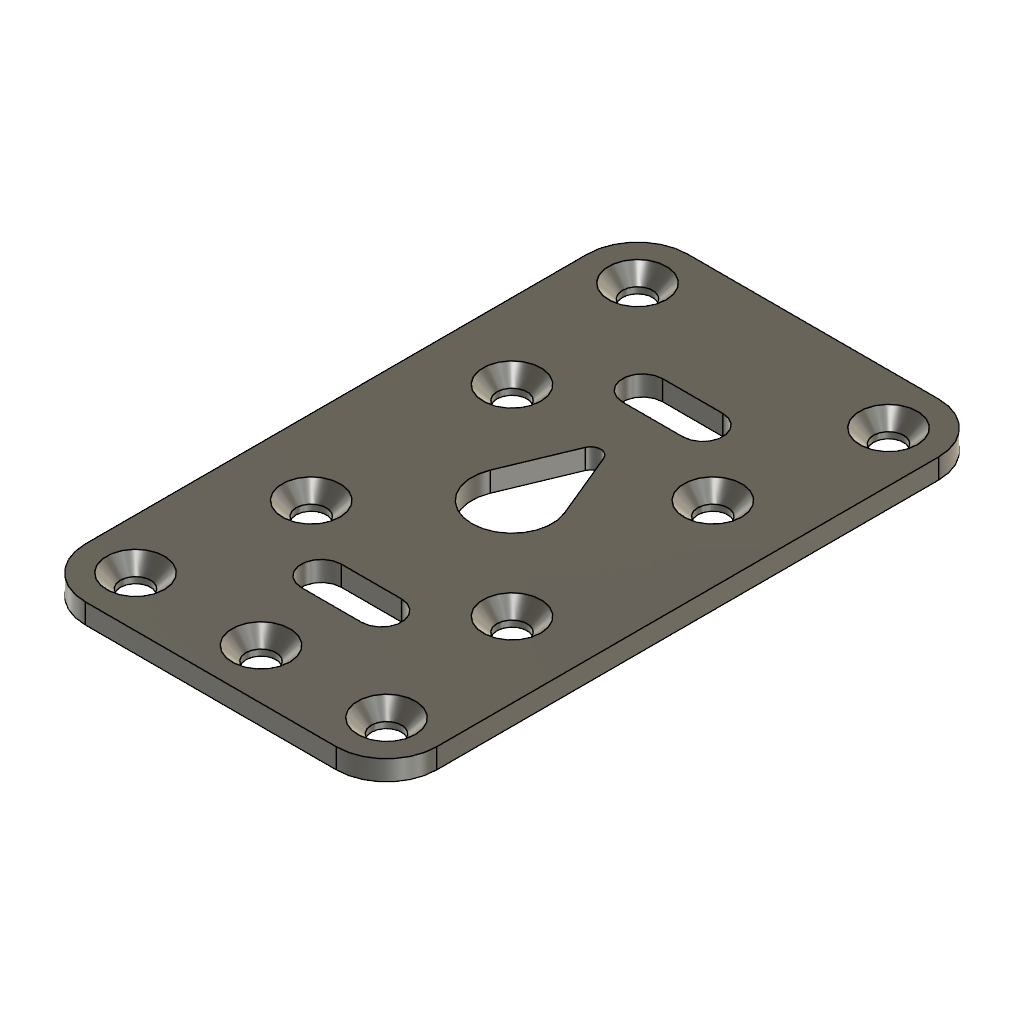
bottom plate (Autodesk Fusion 360 design; units mm, degrees)
part number: 2026-08-28-11-00-39-377
Autodesk Fusion 360 part; units mm, degrees
sketch "Sketch2" plane through (0, 0, 0) normal (0, 0, 1) x (1, 0, 0)
  line L0 (0, 0) -> (35, 0)
  line L1 (35, 0) -> (35, 60)
  line L2 (35, 60) -> (0, 60)
  line L3 (0, 60) -> (0, 0)
  dimension "d1" = 35
  dimension "d2" = 60
  constraint horizontal L0
  constraint vertical L1
  constraint horizontal L2
  constraint vertical L3
  constraint coincident L0.start L3.end
  measures "d1" distance of L0.start L0.end
  measures "d2" distance of L0.end L1.end
extrude "Extrude1" add sketch "Sketch2" along normal blind 2
sketch "Sketch3" plane through (0, 0, 2) normal (0, 0, 1) x (-1, 0, 0)
  line L0 (0, -60) -> (0, 0)
  line L1 (0, 0) -> (-35, 0)
  line L2 (-35, 0) -> (-35, -60)
  line L3 (-35, -60) -> (0, -60)
  point P0 (-5, -5)
  point P1 (-17.5, -5)
  point P2 (-30, -5)
  point P3 (-5, -55)
  point P4 (-30, -55)
  point P5 (-7.5, -40)
  point P6 (-27.5, -40)
  point P7 (-7.5, -20)
  point P8 (-27.5, -20)
  dimension "d5" = 25
  dimension "d6" = 12.5
  dimension "d7" = 25
  dimension "d8" = 5
  dimension "d9" = 5
  dimension "d10" = 5
  dimension "d11" = 5
  dimension "d12" = 20
  dimension "d13" = 20
  dimension "d14" = 20
  dimension "d15" = 7.5
  constraint vertical P5 P7
  constraint vertical P6 P8
  constraint horizontal P7 P8
  constraint horizontal P5 P6
  constraint horizontal P3 P4
  constraint horizontal P0 P1
  constraint horizontal P1 P2
  measures "d5" distance of P0 P2
  measures "d6" distance of P0 P1
  measures "d7" distance of P3 P4
  measures "d8" distance of L0 P3
  measures "d9" distance of L3 P3
  measures "d10" distance of L1 P0
  measures "d11" distance of L0 P0
  measures "d12" distance of P7 P8
  measures "d13" distance of P6 P8
  measures "d14" distance of L1 P8
  measures "d15" distance of L2 P8
hole "Hole1" at (5, 5, 2) at (7.5, 20, 2) at (7.5, 40, 2) at (5, 55, 2) at (30, 55, 2) at (27.5, 40, 2) at (27.5, 20, 2) at (17.5, 5, 2) at (30, 5, 2) direction (0, 0, -1) diameter 3 end through all countersink diameter 5.76 countersink angle 90
fillet "Fillet1" radius 5 4 edges at (0, 0, 1) (35, 0, 1) (35, 60, 1) (0, 60, 1)
sketch "Sketch4" plane through (0, 0, 2) normal (0, 0, 1) x (-1, 0, 0)
  arc A0 (-5, -60) -> (0, -55) centre (-5, -55) ccw
  line L0 (0, -55) -> (0, -5)
  arc A1 (0, -5) -> (-5, 0) centre (-5, -5) ccw
  line L1 (-5, 0) -> (-30, 0)
  arc A2 (-30, 0) -> (-35, -5) centre (-30, -5) ccw
  line L2 (-35, -5) -> (-35, -55)
  arc A3 (-35, -55) -> (-30, -60) centre (-30, -55) ccw
  line L3 (-30, -60) -> (-5, -60)
  circle A4 centre (-30, -5) radius 2.88
  circle A5 centre (-27.5, -20) radius 2.88
  circle A6 centre (-30, -55) radius 2.88
  circle A7 centre (-7.5, -40) radius 2.88
  circle A8 centre (-5, -5) radius 2.88
  circle A9 centre (-7.5, -20) radius 2.88
  circle A10 centre (-5, -55) radius 2.88
  circle A11 centre (-27.5, -40) radius 2.88
  circle A12 centre (-17.5, -5) radius 2.88
  arc A13 (-20.5, -12) -> (-20.5, -16) centre (-20.5, -14) ccw
  arc A14 (-20.5, -44) -> (-20.5, -48) centre (-20.5, -46) ccw
  arc A15 (-14.5, -48) -> (-14.5, -44) centre (-14.5, -46) ccw
  arc A16 (-13.8045, -31.5307) -> (-21.1955, -31.5307) centre (-17.5, -30) ccw
  line L4 (-14.5, -16) -> (-20.5, -16)
  line L5 (-18.4241, -38.2214) -> (-21.1955, -31.5307)
  line L6 (-20.5, -12) -> (-14.5, -12)
  line L7 (-13.8045, -31.5307) -> (-16.576, -38.2218)
  arc A17 (-18.4241, -38.2214) -> (-16.576, -38.2218) centre (-17.5, -37.8394) ccw
  line L8 (-14.5, -48) -> (-20.5, -48)
  line L9 (-20.5, -44) -> (-14.5, -44)
  arc A18 (-14.5, -16) -> (-14.5, -12) centre (-14.5, -14) ccw
  dimension "d22" = 16
  dimension "d24" = 7.8394
  dimension "d25" = 3
  dimension "d26" = 3
  dimension "d27" = 6
  dimension "d28" = 6
  dimension "d29" = 4
  dimension "d30" = 4
  dimension "d31" = 16
  dimension "d32" = 30
  dimension "d33" = 17.5
  constraint vertical A16.centre A17.centre
  constraint horizontal A15.centre A14.centre
  constraint horizontal A13.centre A18.centre
  measures "d22" vertical distance of A16.centre A18.centre
  measures "d24" distance of A16.centre A17.centre
  measures "d25" horizontal distance of A17.centre A15.centre
  measures "d26" horizontal distance of A16.centre A18.centre
  measures "d27" distance of A13.centre A18.centre
  measures "d28" distance of A15.centre A14.centre
  measures "d29" distance of L8 L9
  measures "d30" distance of L4 L6
  measures "d31" vertical distance of A16.centre A15.centre
  measures "d32" distance of L3 A16.centre
  measures "d33" distance of L0 A16.centre
extrude "Extrude2" cut sketch "Sketch4" against normal blind 3 contours A13 L4 L6 A18 | A14 A15 L8 L9 | A16 L5 L7 A17
equation "d6 = ( 25 / 2 ) * 1 mm"
equation "d15 = ( ( 35 - 20 ) / 2 ) * 1 mm"
